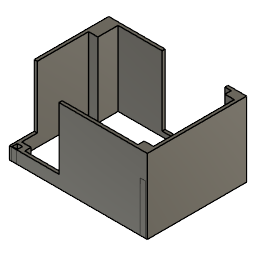
Dumping Container (Autodesk Fusion 360 design; units mm, degrees)
Autodesk Fusion 360 part; units mm, degrees
ref_plane "WorkPlane1" through (0, 0, 25.4) normal (0, 0, 1) x (1, 0, 0)
sketch "Sketch4" plane through (0, 0, 25.4) normal (0, 0, 1) x (1, 0, 0)
  line L0 (0, 0) -> (140.97, 0)
  line L1 (140.97, 0) -> (140.97, 101.6)
  line L2 (140.97, 101.6) -> (0, 101.6)
  line L3 (0, 101.6) -> (0, 0)
  point P0 (140.97, 101.6)
  constraint horizontal L0
  constraint vertical L1
  constraint horizontal L2
  constraint vertical L3
  constraint coincident L0.start L3.end
  constraint coincident P0 L1.end
extrude "Extrude5" add sketch "Sketch4" along normal blind 76.2
sketch "Sketch5" plane through (0, 0, 101.6) normal (0, 0, 1) x (-1, 0, 0)
  line L0 (0, -101.6) -> (0, 0)
  line L1 (0, 0) -> (-140.97, 0)
  line L2 (-140.97, 0) -> (-140.97, -101.6)
  line L3 (-140.97, -101.6) -> (0, -101.6)
  line L4 (-140.97, 0) -> (0, 0)
  line L5 (0, 0) -> (0, -101.6)
  line L6 (0, -101.6) -> (-140.97, -101.6)
  line L7 (-140.97, -101.6) -> (-140.97, 0)
  line L8 (-140.97, 0) -> (-128.27, 0)
  line L9 (-128.27, 0) -> (-128.27, -9.525)
  line L10 (-128.27, -9.525) -> (-140.97, -9.525)
  line L11 (-140.97, -9.525) -> (-140.97, 0)
  line L12 (0, 0) -> (-12.7, 0)
  line L13 (-12.7, 0) -> (-12.7, -9.525)
  line L14 (-12.7, -9.525) -> (0, -9.525)
  line L15 (0, -9.525) -> (0, 0)
  line L16 (0, -101.6) -> (-12.7, -101.6)
  line L17 (-12.7, -101.6) -> (-12.7, -92.075)
  line L18 (-12.7, -92.075) -> (0, -92.075)
  line L19 (0, -92.075) -> (0, -101.6)
  line L20 (-140.97, -101.6) -> (-128.27, -101.6)
  line L21 (-128.27, -101.6) -> (-128.27, -92.075)
  line L22 (-128.27, -92.075) -> (-140.97, -92.075)
  line L23 (-140.97, -92.075) -> (-140.97, -101.6)
  line L24 (-12.7, -101.6) -> (-128.27, -101.6)
  line L25 (-128.27, -101.6) -> (-128.27, -98.425)
  line L26 (-128.27, -98.425) -> (-3.175, -98.425)
  line L27 (-12.7, -98.425) -> (-12.7, -101.6)
  line L28 (-140.97, -92.075) -> (-137.795, -92.075)
  line L29 (-137.795, -92.075) -> (-137.795, -9.525)
  line L30 (-137.795, -9.525) -> (-140.97, -9.525)
  line L31 (-140.97, -9.525) -> (-140.97, -92.075)
  line L32 (-3.175, -9.525) -> (0, -9.525)
  line L33 (0, -9.525) -> (0, -92.075)
  line L34 (0, -92.075) -> (-3.175, -92.075)
  line L35 (-3.175, -98.425) -> (-3.175, -9.525)
  line L36 (-128.27, 0) -> (-12.7, 0)
  line L37 (-12.7, 0) -> (-12.7, -3.175)
  line L38 (-12.7, -3.175) -> (-128.27, -3.175)
  line L39 (-128.27, -3.175) -> (-128.27, 0)
  line L40 (-12.7, -98.425) -> (-12.7, -77.8256)
  line L41 (-12.7, -77.8256) -> (-3.175, -77.8256)
  dimension "d82" = 12.7
  dimension "d83" = 9.525
  dimension "d84" = 9.525
  dimension "d85" = 12.7
  dimension "d86" = 9.525
  dimension "d87" = 12.7
  dimension "d88" = 9.525
  dimension "d89" = 12.7
  dimension "d90" = 3.175
  dimension "d91" = 3.175
  dimension "d92" = 3.175
  dimension "d93" = 3.175
  dimension "d120" = 20.5994
  constraint horizontal L4
  constraint vertical L5
  constraint horizontal L6
  constraint vertical L7
  constraint coincident L0.start L3.end
  constraint coincident L1.end L2.start
  constraint horizontal L8
  constraint vertical L9
  constraint horizontal L10
  constraint vertical L11
  constraint horizontal L12
  constraint vertical L13
  constraint horizontal L14
  constraint vertical L15
  constraint coincident L0.end L1.start
  constraint horizontal L16
  constraint vertical L17
  constraint horizontal L18
  constraint vertical L19
  constraint horizontal L20
  constraint vertical L21
  constraint horizontal L22
  constraint vertical L23
  constraint coincident L2.end L3.start
  constraint horizontal L24
  constraint vertical L25
  constraint horizontal L26
  constraint vertical L27
  constraint coincident L21 L25.end
  constraint horizontal L28
  constraint vertical L29
  constraint horizontal L30
  constraint vertical L31
  constraint horizontal L32
  constraint vertical L33
  constraint horizontal L34
  constraint vertical L35
  constraint horizontal L36
  constraint vertical L37
  constraint horizontal L38
  constraint vertical L39
  constraint coincident L10 L11.start
  constraint coincident L13 L37.end
  constraint coincident L14 L32.start
  constraint coincident L34.end L35
  constraint coincident L27.start L26
  constraint perpendicular L18 L40
  constraint coincident L35 L41.end
  constraint perpendicular L35 L41
  measures "d82" distance of L7 L21
  measures "d83" distance of L6 L22
  measures "d84" distance of L4 L10
  measures "d85" distance of L7 L9
  measures "d86" distance of L12 L14
  measures "d87" distance of L5 L13
  measures "d88" distance of L6 L18
  measures "d89" distance of L5 L17
  measures "d90" distance of L24 L26
  measures "d91" distance of L29 L31
  measures "d92" distance of L36 L38
  measures "d93" distance of L33 L35
  measures "d120" distance of L27.start L40.end
extrude "Extrude8" cut sketch "Sketch5" against normal blind 76.2 contours L9 L10 L13 L14 L17 L21 L22 L26 L29 L35 L38 L40 L41
sketch "Sketch6" plane through (0, 0, 25.4) normal (0, 0, -1) x (1, 0, 0)
  line L0 (0, 0) -> (0, -101.6)
  line L1 (0, -101.6) -> (140.97, -101.6)
  line L2 (140.97, -101.6) -> (140.97, 0)
  line L3 (140.97, 0) -> (0, 0)
  line L4 (0, 0) -> (140.97, 0)
  line L5 (140.97, 0) -> (140.97, -101.6)
  line L6 (140.97, -101.6) -> (0, -101.6)
  line L7 (0, -101.6) -> (0, 0)
  line L8 (2.286, -0.635) -> (7.493, -0.635)
  line L9 (7.493, -0.635) -> (7.493, -5.842)
  line L10 (7.493, -5.842) -> (2.286, -5.842)
  line L11 (2.286, -5.842) -> (2.286, -0.635)
  line L12 (133.477, -5.842) -> (133.477, -0.635)
  line L13 (133.477, -0.635) -> (138.684, -0.635)
  line L14 (138.684, -5.842) -> (133.477, -5.842)
  line L15 (138.684, -0.635) -> (138.684, -5.842)
  line L16 (2.286, -100.965) -> (2.286, -95.5487)
  line L17 (2.286, -95.5487) -> (7.4888, -95.758)
  line L18 (7.4886, -100.965) -> (2.286, -100.965)
  line L19 (7.4888, -95.758) -> (7.4886, -100.965)
  line L20 (133.477, -100.965) -> (133.477, -95.758)
  line L21 (133.477, -95.758) -> (138.684, -95.758)
  line L22 (138.684, -100.965) -> (133.477, -100.965)
  line L23 (138.684, -95.758) -> (138.684, -100.965)
  line L24 (12.7, -3.175) -> (128.27, -3.175)
  line L25 (128.27, -3.175) -> (128.27, -9.525)
  line L26 (128.27, -9.525) -> (137.795, -9.525)
  line L27 (137.795, -9.525) -> (137.795, -92.075)
  line L28 (137.795, -92.075) -> (128.27, -92.075)
  line L29 (128.27, -92.075) -> (128.27, -98.425)
  line L30 (128.27, -98.425) -> (12.7, -98.425)
  line L31 (12.7, -98.425) -> (12.7, -77.8256)
  line L32 (3.175, -77.8256) -> (3.175, -9.525)
  line L33 (3.175, -9.525) -> (12.7, -9.525)
  line L34 (12.7, -9.525) -> (12.7, -3.175)
  line L35 (12.7, -77.8256) -> (3.175, -77.8256)
  dimension "d96" = 5.207
  dimension "d97" = 5.207
  dimension "d98" = 0.635
  dimension "d99" = 2.286
  dimension "d104" = 5.207
  dimension "d105" = 5.207
  dimension "d106" = 0.635
  dimension "d107" = 5.207
  dimension "d108" = 5.207
  dimension "d109" = 2.286
  dimension "d110" = 5.207
  dimension "d111" = 5.207
  constraint horizontal L4
  constraint vertical L5
  constraint horizontal L6
  constraint vertical L7
  constraint coincident L1.end L2.start
  constraint coincident L0.start L3.end
  constraint horizontal L8
  constraint vertical L9
  constraint horizontal L10
  constraint vertical L11
  constraint collinear L18 L22
  constraint collinear L15 L23
  constraint collinear L8 L13
  constraint collinear L11 L16
  measures "d96" distance of L8.start L10.end
  measures "d97" distance of L8.start L8.end
  measures "d98" distance of L4 L8
  measures "d99" distance of L7 L11
  measures "d104" distance of L17.end L18.start
  measures "d105" distance of L16.end L17.end
  measures "d106" distance of L6 L18
  measures "d107" distance of L20.start L22.start
  measures "d108" distance of L21.end L22.start
  measures "d109" distance of L5 L23
  measures "d110" distance of L13.end L14.start
  measures "d111" distance of L12.start L14.start
extrude "Extrude9" cut sketch "Sketch6" against normal blind 50.8 contours L8 L9 L10 L11 | L12 L13 L14 L15 | L16 L17 L18 L19 | L20 L21 L22 L23
sketch "Sketch7" plane through (0, 0, 0) normal (0, -1, 0) x (1, 0, 0)
  line L0 (0, 25.4) -> (140.97, 25.4)
  line L1 (140.97, 25.4) -> (140.97, 101.6)
  line L2 (140.97, 101.6) -> (0, 101.6)
  line L3 (0, 101.6) -> (0, 25.4)
  line L4 (0, 101.6) -> (50.8, 101.6)
  line L5 (50.8, 101.6) -> (50.8, 38.1)
  line L6 (50.8, 38.1) -> (0, 38.1)
  line L7 (0, 38.1) -> (0, 101.6)
  dimension "d115" = 50.8
  dimension "d118" = 63.5
  constraint horizontal L4
  constraint vertical L5
  constraint horizontal L6
  constraint vertical L7
  constraint coincident L2.end L3.start
  measures "d115" distance of L5.end L6.end
  measures "d118" distance of L4.end L5.end
extrude "Extrude10" cut sketch "Sketch7" against normal blind 25.4 contours L2 L3 L4 L5 L6 L7
sketch "Sketch8" plane through (0, 101.6, 0) normal (0, 1, 0) x (-1, 0, 0)
  line L0 (-140.97, 25.4) -> (0, 25.4)
  line L1 (0, 25.4) -> (0, 101.6)
  line L2 (0, 101.6) -> (-140.97, 101.6)
  line L3 (-140.97, 101.6) -> (-140.97, 25.4)
  line L4 (0, 101.6) -> (-57.658, 101.6) construction
  line L5 (-57.658, 101.6) -> (-121.7676, 101.6)
  line L6 (-121.7676, 101.6) -> (-121.7676, 30.48)
  line L7 (-121.7676, 30.48) -> (-57.658, 30.48)
  line L8 (-57.658, 30.48) -> (-57.658, 101.6)
  dimension "d121" = 57.658
  dimension "d124" = 64.1096
  dimension "d125" = 71.12
  constraint coincident L1.end L2.start
  constraint perpendicular L1 L4
  constraint horizontal L5
  constraint vertical L6
  constraint horizontal L7
  constraint vertical L8
  measures "d121" distance of L1.end L4.end
  measures "d124" distance of L6.end L7.end
  measures "d125" distance of L5.end L6.end
extrude "Extrude11" cut sketch "Sketch8" against normal up to surface (3.175 mm away) contours L2 L5 L6 L7 L8
equation "d124 = 3.03 in - 0.506 in"
